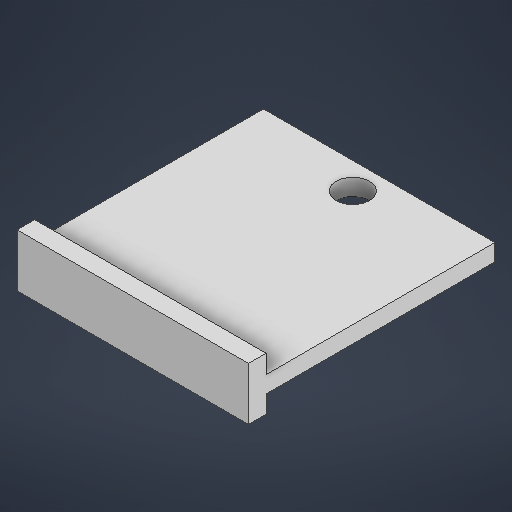
# Autodesk Inventor part: tingv2
Saved by Autodesk Inventor 2026.1 (Build 301233020, 233B)
## iProperties
Created: 2026-03-22
Part Number: tingv2
Material: Generic
Document SubType Name: Modeling
Designer: runek
Density: 1 g/cm^3
Appearance: Default
Author: runek
Autodesk Inventor part; units mm, degrees
ref_plane "YZ Plane" through (0, 0, 0) normal (1, 0, 0) x (0, 1, 0)
ref_plane "XZ Plane" through (0, 0, 0) normal (0, 1, 0) x (-1, 0, 0)
ref_plane "XY Plane" through (0, 0, 0) normal (0, 0, 1) x (1, 0, 0)
sketch "Sketch1" plane through (0, 0, 0) normal (0, 1, 0) x (-1, 0, 0)
  line L0 (0, 0) -> (26.3, 0)
  line L1 (26.3, 0) -> (26.3, 26)
  line L2 (26.3, 26) -> (0, 26)
  line L3 (0, 26) -> (0, 0)
  line L4 (26.3, 26) -> (0, 26)
  line L5 (0, 26) -> (0, 6)
  line L6 (0, 6) -> (26.3, 6)
  line L7 (26.3, 6) -> (26.3, 26)
  line L8 (26.3, 26) -> (0, 26)
  line L9 (0, 26) -> (0, 28)
  line L10 (0, 28) -> (26.3, 28)
  line L11 (26.3, 28) -> (26.3, 26)
  line L12 (26.3, 6) -> (0, 6)
  line L13 (13.15, 0) -> (13.15, 3)
  circle A0 centre (13.15, 3) radius 1.9
  point P0 (0, 26)
  dimension "d0" = 26.3
  dimension "d1" = 26
  dimension "d2" = 20
  dimension "d3" = 2
  dimension "d4" = 3
  dimension "d5" = 3.8
  constraints: 28 end point, 6 parallel, 4 perpendicular, 3 horizontal, 1 centre point, 1 coincident, 1 midpoint, 1 point on line, 1 vertical
  measures "d0" distance of L2.end L1.end
  measures "d1" distance of L1.end L0.end
  measures "d2" distance of L5.end L4.end
  measures "d3" distance of L8.end L9.end
  measures "d4" distance of L13.start L13.end
  measures "d5" diameter of A0
extrude "Extrusion1" add sketch "Sketch1" along normal blind 1.9 contours L3 L6 L1 L0 | L3 L2 L1 L6
extrude "Extrusion2" add sketch "Sketch1" along normal blind 4 contours L9 L10 L11 L2
extrude "Extrusion3" add sketch "Sketch1" against normal blind 2 contours L9 L10 L11 L2
body "Solid1"
